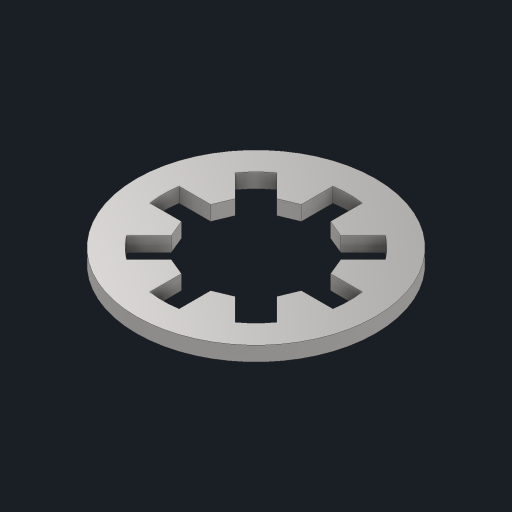
# Autodesk Inventor part: Arruela de pressão dentada interna ASME B18.21.1 No.10 Tipo A
Saved by Autodesk Inventor 2024.3 (Build 283343000, 343)
## iProperties
Created: 2025-02-16
Part Number: Arruela de pressão dentada interna ASME B18.21.1 No.10 Tipo A
Material: Aço, carbono
Document SubType Name: Modeling
Designer: Cliente
Density: 7.85 g/cm^3
Appearance: Inoxidável - Escovado
Mass: 0.203357 g
Surface Area: 1.26745 cm^2
Volume: 0.0259054 cm^3
Author: Cliente
Autodesk Inventor part; units mm, degrees
ref_plane "YZ Plane" through (0, 0, 0) normal (1, 0, 0) x (0, 1, 0)
ref_plane "XZ Plane" through (0, 0, 0) normal (0, 1, 0) x (-1, 0, 0)
ref_plane "XY Plane" through (0, 0, 0) normal (0, 0, 1) x (1, 0, 0)
sketch "Esboço1" plane through (0, 0, 0) normal (0, 1, 0) x (-1, 0, 0)
  circle A0 centre (0, 0) radius 4.9
  circle A1 centre (0, 0) radius 3.8
  line L0 (-0.6, 3.8) -> (0.6, 3.8)
  line L1 (0.6, 3.8) -> (0.6, -3.8)
  line L2 (0.6, -3.8) -> (-0.6, -3.8)
  line L3 (-0.6, -3.8) -> (-0.6, 3.8)
  line L4 (-0.6, 3.8) -> (0.6, -3.8) construction
  line L5 (0.6, 3.8) -> (-0.6, -3.8) construction
  line L6 (-2.2627, 3.1113) -> (3.1113, -2.2627)
  line L7 (2.2627, -3.1113) -> (-3.1113, 2.2627)
  line L8 (-3.8, 0.6) -> (3.8, 0.6)
  line L9 (3.8, -0.6) -> (-3.8, -0.6)
  line L10 (-3.1113, -2.2627) -> (2.2627, 3.1113)
  line L11 (3.1113, 2.2627) -> (-2.2627, -3.1113)
  line L12 (-0.6, -3.8) -> (-0.6, 3.8)
  line L13 (0.6, 3.8) -> (0.6, -3.8)
  line L14 (2.2627, -3.1113) -> (-3.1113, 2.2627)
  line L15 (-2.2627, 3.1113) -> (3.1113, -2.2627)
  line L16 (3.8, -0.6) -> (-3.8, -0.6)
  line L17 (-3.8, 0.6) -> (3.8, 0.6)
  line L18 (3.1113, 2.2627) -> (-2.2627, -3.1113)
  line L19 (-3.1113, -2.2627) -> (2.2627, 3.1113)
  line L20 (3.1113, -2.2627) -> (3.8, -0.6)
  line L21 (3.4556, -1.4314) -> (3.5107, -1.4542)
  line L22 (3.5107, -1.4542) -> (2.3097, -0.9567)
  line L23 (2.3097, -0.9567) -> (2.1619, -1.3134)
  line L24 (2.3097, -0.9567) -> (2.4575, -0.6)
  line L25 (2.3097, 0.9567) -> (2.4575, 0.6)
  line L26 (2.3097, 0.9567) -> (2.1619, 1.3134)
  line L27 (0.9567, 2.3097) -> (1.3134, 2.1619)
  line L28 (0.9567, 2.3097) -> (0.6, 2.4575)
  line L29 (-0.9567, 2.3097) -> (-0.6, 2.4575)
  line L30 (-0.9567, 2.3097) -> (-1.3134, 2.1619)
  line L31 (-2.3097, 0.9567) -> (-2.1619, 1.3134)
  line L32 (-2.3097, 0.9567) -> (-2.4575, 0.6)
  line L33 (-2.3097, -0.9567) -> (-2.4575, -0.6)
  line L34 (-2.3097, -0.9567) -> (-2.1619, -1.3134)
  line L35 (-0.9567, -2.3097) -> (-1.3134, -2.1619)
  line L36 (-0.9567, -2.3097) -> (-0.6, -2.4575)
  line L37 (0.9567, -2.3097) -> (0.6, -2.4575)
  line L38 (0.9567, -2.3097) -> (1.3134, -2.1619)
  point P0 (3.0776, -2.229)
  point P1 (2.229, -3.0776)
  point P2 (1.3134, -2.1619)
  point P3 (0.6, -2.4575)
  point P4 (-0.6, -2.4575)
  point P5 (-1.3134, -2.1619)
  point P6 (-2.229, -3.0776)
  point P7 (-3.0776, -2.229)
  point P8 (-2.1619, -1.3134)
  point P9 (-2.4575, -0.6)
  point P10 (-3.7523, -0.6)
  point P11 (-3.7523, 0.6)
  point P12 (-2.4575, 0.6)
  point P13 (-2.1619, 1.3134)
  point P14 (-3.0776, 2.229)
  point P15 (-2.229, 3.0776)
  point P16 (-1.3134, 2.1619)
  point P17 (-0.6, 2.4575)
  point P18 (0.6, 2.4575)
  point P19 (1.3134, 2.1619)
  point P20 (2.229, 3.0776)
  point P21 (3.0776, 2.229)
  point P22 (2.1619, 1.3134)
  point P23 (2.4575, 0.6)
  point P24 (3.7523, 0.6)
  point P25 (3.7523, -0.6)
  point P26 (2.4575, -0.6)
  point P27 (2.1619, -1.3134)
  point P28 (-0.6, -3.7523)
  point P29 (0, -3.8)
  point P30 (0.6, -3.7523)
  point P31 (-0.6, 3.7523)
  point P32 (0, 3.8)
  point P33 (0.6, 3.7523)
  dimension "d1" = 9.8
  dimension "d2" = 1.1
  dimension "d3" = 1.2
  dimension "d6" = 360
  dimension "d8" = 1.3
  dimension "d11" = 360
  constraints: 78 end point, 11 point on line, 3 midpoint, 3 perpendicular, 2 horizontal, 2 parallel, 1 centre point, 1 coincident, 93 other
  measures "d1" diameter of A0
  measures "d3" distance of L1.end L2.end
  measures "d8" distance of L21.end L22.end
extrude "Extrusão1" add sketch "Esboço1" along normal blind 0.6 contours A0 | L8 L25 L26 L11 A1 | L9 L20 A1 | A1 L20 L22 L24 L9 | A1 L21 L20 | L10 L27 L28 L1 A1 | A1 L20 L21 | L20 A1 L6 L23 L22 | A1 L0 L1 | L20 L6 A1 | A1 L3 L0 | L3 L29 L30 L6 A1 | A1 L1 L37 L38 L7 | L1 L2 A1 | L7 L31 L32 L8 A1 | L2 L3 A1 | L3 A1 L11 L35 L36 | L33 L34 L10 A1 L9
